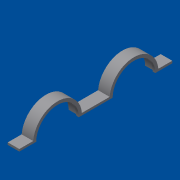
# Autodesk Inventor part: truss upper v5
Saved by Autodesk Inventor 2019 (Build 230136000, 136)
## iProperties
Created: 2019-04-16
Part Number: truss upper v5
Material: Generic
Document SubType Name: Modeling
Designer: Dell
Density: 1 g/cm^3
Appearance: Default
Author: Dell
Autodesk Inventor part; units mm, degrees
ref_plane "YZ Plane" through (0, 0, 0) normal (1, 0, 0) x (0, 1, 0)
ref_plane "XZ Plane" through (0, 0, 0) normal (0, 1, 0) x (-1, 0, 0)
ref_plane "XY Plane" through (0, 0, 0) normal (0, 0, 1) x (1, 0, 0)
sketch "Sketch1" plane through (0, 0, 0) normal (1, 0, 0) x (0, 1, 0)
  arc A0 (0, -25.5) -> (0, 25.5) centre (0, 0) ccw
  arc A1 (2.5, -27.3861) -> (2.5, 27.3861) centre (0, 0) ccw
  line L0 (0, 0) -> (4.8252, 0)
  line L1 (2.5, 27.3861) -> (2.5, 43)
  line L2 (2.5, 43) -> (0, 43)
  line L3 (0, 43) -> (0, 25.5)
  line L4 (0, 27.5) -> (0, 25.5)
  line L5 (0, 0) -> (2.5, 0)
  line L6 (2.5, -27.3861) -> (2.5, -43)
  line L7 (2.5, -43) -> (0, -43)
  line L8 (0, -43) -> (0, -25.5)
  dimension "d0" = 51
  dimension "d1" = 55
  dimension "d2" = 43
  dimension "d3" = 2.5
  dimension "d4" = 43
  dimension "d5" = 2.5
  constraints: 18 end point, 4 parallel, 4 point on circle, 2 centre point, 2 coincident, 2 horizontal, 2 perpendicular, 1 vertical
  measures "d0" diameter of A0
  measures "d1" diameter of A1
  measures "d2" distance from line of L2 point (0, 0)
  measures "d3" distance between parallel lines of L3 L1
  measures "d4" distance between parallel lines of L7 L0
  measures "d5" distance between parallel lines of L8 L6
extrude "Extrusion1" add sketch "Sketch1" along normal blind 10
sketch "Sketch2" plane through (10, 0, 0) normal (1, 0, 0) x (0, 0, -1)
  arc A0 (27.3861, 2.5) -> (-27.3861, 2.5) centre (0, 0) ccw projected
  line L0 (-27.3861, 2.5) -> (-43, 2.5) projected
  line L1 (-43, 2.5) -> (-43, 0) projected
  line L2 (-43, 0) -> (-25.5, 0) projected
  arc A1 (25.5, 0) -> (-25.5, 0) centre (0, 0) ccw projected
  line L3 (25.5, 0) -> (43, 0) projected
  line L4 (43, 0) -> (43, 2.5) projected
  line L5 (43, 2.5) -> (27.3861, 2.5) projected
  arc A2 (24, 0) -> (-24, 0) centre (0, 0) ccw
  line L6 (-43, 0) -> (-25.5, 0) projected
  line L7 (-43, 0) -> (-24, 0)
  line L8 (24, 0) -> (43, 0)
  dimension "d8" = 48
  constraints: 4 end point, 2 collinear, 2 point on circle, 1 centre point, 1 coincident
  measures "d8" diameter of A2
extrude "Extrusion2" add sketch "Sketch2" along normal blind 3
mirror "Mirror1" about plane through (0, 2.5, 43) normal (0, 0, 1) of "Extrusion1", "Extrusion2"
body "Solid1"
